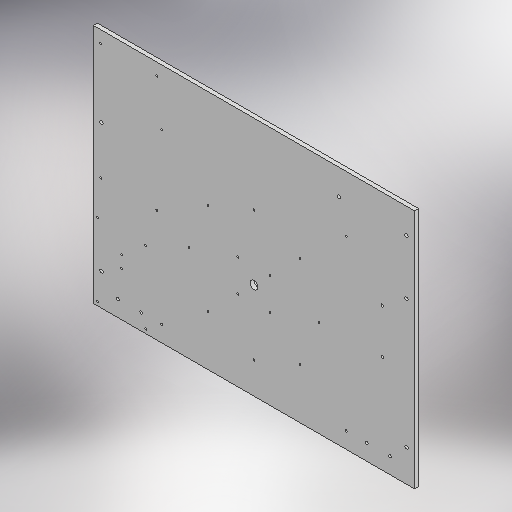
# Autodesk Inventor part: base_plate
Saved by Autodesk Inventor 2025.3 (Build 293356030, 356C)
## iProperties
Created: 2025-08-02
Part Number: base_plate
Material: 一般
Document SubType Name: Modeling
Designer: ibuki_ono
Density: 1 g/cm^3
Appearance: 既定
Author: ibuki_ono
Autodesk Inventor part; units mm, degrees
ref_plane "YZ Plane" through (0, 0, 0) normal (1, 0, 0) x (0, 1, 0)
ref_plane "XZ Plane" through (0, 0, 0) normal (0, 1, 0) x (-1, 0, 0)
ref_plane "XY Plane" through (0, 0, 0) normal (0, 0, 1) x (1, 0, 0)
sketch "スケッチ1" plane through (0, 0, 0) normal (0, 0, 1) x (1, 0, 0)
  line L0 (-200, -150) -> (200, -150)
  line L1 (200, -150) -> (200, 150)
  line L2 (200, 150) -> (-200, 150)
  line L3 (-200, 150) -> (-200, -150)
  line L4 (-200, -150) -> (200, 150) construction
  line L5 (200, -150) -> (-200, 150) construction
  point P0 (0, 0)
  dimension "d0" = 400
  dimension "d1" = 300
  constraints: 12 end point, 2 midpoint, 2 parallel, 1 horizontal, 1 perpendicular
  measures "d0" distance of L2.end L1.end
  measures "d1" distance of L1.end L0.end
extrude "押し出し1" add sketch "スケッチ1" along normal blind 5
sketch "スケッチ6" plane through (0, 0, 0) normal (0, 0, -1) x (-1, 0, 0)
  line L0 (-169.5, -130) -> (-140.5, -130) construction
  line L1 (-169.5, -130) -> (-140.5, -130) construction
  line L2 (200, -150) -> (-200, -150) construction
  line L3 (-200, -150) -> (-200, 150) construction
  point P0 (0, 0)
  point P1 (-155, -130)
  dimension "d51" = 29
  dimension "d52" = 0
  dimension "d53" = 20
  dimension "d54" = 45
  constraints: 4 end point, 2 coincident, 2 horizontal, 1 collinear, 1 midpoint
  measures "d51" distance of L0.start L0.end
  measures "d52" distance between parallel lines of L0 L1
  measures "d53" distance between parallel lines of L2 L0
  measures "d54" distance from line of L3 point (-155, -130)
hole "穴5" at (140.5, -130, 0) at (169.5, -130, 0) direction (0, 0, 1) diameter 3.5 end through all
mirror "ミラー1" about plane through (0, 0, 0) normal (1, 0, 0) of "穴5"
sketch "スケッチ10" plane through (0, 0, 5) normal (0, 0, 1) x (1, 0, 0)
  circle A0 centre (0, -30) radius 81 construction
  line L0 (0, 51) -> (0, -30) construction
  line L1 (0, -30) -> (-57.2756, 27.2756) construction
  line L2 (0, -30) -> (57.2756, 27.2756) construction
  line L3 (0, -30) -> (81, -30) construction
  line L4 (0, -30) -> (0, -111) construction
  line L5 (0, -30) -> (81, -30) construction
  line L6 (0, -30) -> (-81, -30) construction
  line L7 (0, -30) -> (-57.2756, -87.2756) construction
  line L8 (0, -30) -> (81, -30) construction
  line L9 (0, -30) -> (57.2756, -87.2756) construction
  line L10 (0, -30) -> (81, -30) construction
  point P0 (0, 0)
  dimension "d95" = 162
  dimension "d96" = 30
  dimension "d97" = 45
  dimension "d98" = 45
  dimension "d99" = 135
  dimension "d100" = 45
  constraints: 22 end point, 4 coincident, 3 equal length, 3 horizontal, 2 collinear, 2 vertical, 1 vertical alignment, 10 other
  measures "d96" distance of point (0, 0) L0.end
  measures "d97" angle of L0 L1
  measures "d98" angle of L3 L2
  measures "d99" angle of L7 L8
  measures "d100" angle of L9 L10
hole "穴9" at (0, 51, 5) at (0, -111, 5) at (-81, -30, 5) at (81, -30, 5) at (-57.2756, 27.2756, 5) at (-57.2756, -87.2756, 5) at (57.2756, -87.2756, 5) at (57.2756, 27.2756, 5) direction (0, 0, -1) diameter 2.5 end through all
sketch "スケッチ11" plane through (0, 0, 5) normal (0, 0, 1) x (1, 0, 0)
  circle A0 centre (0, 51) radius 1.25 projected
  circle A1 centre (0, -111) radius 1.25 projected
  line L0 (0, -111) -> (0, 51) construction
  circle A2 centre (0, -30) radius 5
  point P0 (0, 0)
  dimension "d108" = 10
  constraints: 2 end point, 1 centre point, 1 midpoint, 1 vertical
  measures "d108" diameter of A2
extrude "押し出し2" cut sketch "スケッチ11" against normal through all contours A2
sketch "スケッチ12" plane through (0, 0, 5) normal (0, 0, 1) x (1, 0, 0)
  circle A0 centre (0, -30) radius 5 projected
  line L0 (-20, -50) -> (20, -50) construction
  line L1 (20, -50) -> (20, -10) construction
  line L2 (20, -10) -> (-20, -10) construction
  line L3 (-20, -10) -> (-20, -50) construction
  line L4 (-20, -50) -> (20, -10) construction
  line L5 (20, -50) -> (-20, -10) construction
  point P0 (0, 0)
  dimension "d111" = 40
  dimension "d112" = 40
  constraints: 12 end point, 4 coincident, 2 midpoint, 2 parallel, 1 horizontal, 1 perpendicular
  measures "d111" distance of L2.end L1.end
  measures "d112" distance of L1.end L0.end
hole "穴10" at (-20, -10, 5) at (20, -10, 5) at (20, -50, 5) at (-20, -50, 5) direction (0, 0, -1) diameter 2.5 end through all
sketch "スケッチ13" plane through (0, 0, 5) normal (0, 0, 1) x (1, 0, 0)
  line L0 (-200, -150) -> (200, -150) projected
  line L1 (-115, -150) -> (-115, 80) construction
  point P0 (0, 0)
  point P1 (-115, -130)
  dimension "d120" = 230
  dimension "d121" = 115
  dimension "d122" = 210
  constraints: 2 end point, 2 point on line, 1 coincident, 1 vertical
  measures "d120" distance of L1.start L1.end
  measures "d121" distance from line of point (0, 0) L1
  measures "d122" distance of point (-115, -130) point (-115, 80)
hole "穴11" at (-115, 80, 5) at (-115, -130, 5) direction (0, 0, -1) diameter 2.5 end through all
mirror "ミラー2" about plane through (0, 0, 0) normal (1, 0, 0) of "穴11"
sketch "スケッチ14" plane through (0, 0, 5) normal (0, 0, 1) x (1, 0, 0)
  line L0 (-200, -150) -> (200, -150) projected
  line L1 (-190, -150) -> (-190, 50) construction
  line L2 (-190, -150) -> (10, -150) construction
  line L3 (-200, 150) -> (-200, -150) construction
  point P0 (0, 0)
  point P1 (-190, -110)
  dimension "d130" = 200
  dimension "d131" = 90
  dimension "d132" = 10
  dimension "d133" = 160
  constraints: 4 end point, 2 point on line, 1 coincident, 1 horizontal, 1 perpendicular, 1 vertical
  measures "d130" distance of L1.start L1.end
  measures "d131" angle of L2 L1
  measures "d132" distance between parallel lines of L3 L1
  measures "d133" distance of point (-190, -110) point (-190, 50)
hole "穴12" at (-190, 50, 5) at (-190, -110, 5) direction (0, 0, -1) diameter 4.2 end through all
mirror "ミラー3" about plane through (0, 0, 0) normal (1, 0, 0) of "穴12"
sketch "スケッチ15" plane through (0, 0, 5) normal (0, 0, 1) x (1, 0, 0)
  line L0 (-200, -150) -> (200, -150) projected
  line L1 (-165, -150) -> (-165, -80) construction
  line L2 (-200, 150) -> (-200, -150) construction
  point P0 (0, 0)
  point P1 (-165, -95)
  dimension "d141" = 70
  dimension "d142" = 35
  dimension "d143" = 15
  constraints: 2 end point, 2 point on line, 1 coincident, 1 vertical
  measures "d141" distance of L1.start L1.end
  measures "d142" distance between parallel lines of L2 L1
  measures "d143" distance of point (-165, -80) point (-165, -95)
hole "穴13" at (-165, -80, 5) at (-165, -95, 5) direction (0, 0, -1) diameter 2.5 end through all
sketch "スケッチ16" plane through (0, 0, 5) normal (0, 0, 1) x (1, 0, 0)
  line L0 (200, 150) -> (-200, 150) projected
  line L1 (200, -150) -> (200, 150) projected
  line L2 (106, 118) -> (190, 118) construction
  line L3 (106, 118) -> (190, 118) construction
  point P0 (0, 0)
  dimension "d151" = 84
  dimension "d152" = 0
  dimension "d153" = 32
  dimension "d154" = 10
  constraints: 4 end point, 2 horizontal, 1 collinear
  measures "d151" distance of L2.start L2.end
  measures "d152" distance between parallel lines of L2 L3
  measures "d153" distance between parallel lines of L0 L2
  measures "d154" distance from line of L1 L2.end
hole "穴14" at (106, 118, 5) at (190, 118, 5) direction (0, 0, -1) diameter 4.2 end through all
sketch "スケッチ17" plane through (0, 0, 5) normal (0, 0, 1) x (1, 0, 0)
  line L0 (160, 27.85) -> (160, -27.85) construction
  line L1 (160, 27.85) -> (215.7, 27.85) construction
  line L2 (200, -150) -> (200, 150) construction
  point P0 (0, 0)
  point P1 (160, 0)
  dimension "d162" = 55.7
  dimension "d163" = 90
  dimension "d164" = 40
  constraints: 4 end point, 1 horizontal, 1 horizontal alignment, 1 midpoint, 1 perpendicular, 1 vertical
  measures "d162" distance of L0.start L0.end
  measures "d163" angle of L0 L1
  measures "d164" distance between parallel lines of L2 L0
hole "穴15" at (160, 27.85, 5) at (160, -27.85, 5) direction (0, 0, -1) diameter 3.3 end through all
sketch "スケッチ18" plane through (0, 0, 5) normal (0, 0, 1) x (1, 0, 0)
  line L0 (-195, -145) -> (-135, -145) construction
  line L1 (-135, -145) -> (-135, -55) construction
  line L2 (-135, -55) -> (-195, -55) construction
  line L3 (-195, -55) -> (-195, -145) construction
  line L4 (-195, -145) -> (-135, -55) construction
  line L5 (-135, -145) -> (-195, -55) construction
  line L6 (-200, 150) -> (-200, -150) construction
  line L7 (-200, -150) -> (200, -150) construction
  line L8 (-191, -10) -> (-121, -10) construction
  line L9 (-121, -10) -> (-121, 135) construction
  line L10 (-121, 135) -> (-191, 135) construction
  line L11 (-191, 135) -> (-191, -10) construction
  line L12 (-191, -10) -> (-121, 135) construction
  line L13 (-121, -10) -> (-191, 135) construction
  line L14 (200, 150) -> (-200, 150) construction
  point P0 (0, 0)
  point P1 (-165, -100)
  point P2 (-156, 62.5)
  dimension "d172" = 60
  dimension "d173" = 90
  dimension "d174" = 5
  dimension "d175" = 5
  dimension "d183" = 70
  dimension "d184" = 145
  dimension "d185" = 9
  dimension "d186" = 15
  constraints: 24 end point, 8 coincident, 4 midpoint, 4 parallel, 2 horizontal, 2 perpendicular
  measures "d172" distance of L2.end L1.end
  measures "d173" distance of L1.end L0.end
  measures "d174" distance between parallel lines of L6 L3
  measures "d175" distance between parallel lines of L7 L0
  measures "d183" distance of L10.end L9.end
  measures "d184" distance of L9.end L8.end
  measures "d185" distance between parallel lines of L6 L11
  measures "d186" distance between parallel lines of L14 L10
hole "穴16" at (-195, -55, 5) at (-135, -55, 5) at (-135, -145, 5) at (-195, -145, 5) at (-191, -10, 5) at (-121, -10, 5) at (-121, 135, 5) at (-191, 135, 5) direction (0, 0, -1) diameter 2.5 end through all
equation "\"d175\" = d174"
